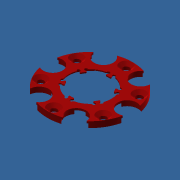
# Autodesk Inventor part: 15-0012-0330
Saved by Autodesk Inventor 2016 SP2 (Build 200236200, 236)
## iProperties
Created: 2017-10-24
Part Number: 15-0012-0330
Material: Plastic (PEEK)
Document SubType Name: Modeling
Designer: Hans Ellermeijer
Density: 1.32 g/cm^3
Appearance: Red
User Status: CNC
Project: Quantum Gas Microscope
Cost Center: 15-0012
Authority: Georgios Siviloglou
Mass: 1.27585 g
Surface Area: 19.8517 cm^2
Volume: 0.966551 cm^3
Description: Aandruk Ring
Category: IOP
Company: Universiteit van Amsterdam
Author: Hans Ellermeijer
Revision Number: A.1
Title: Quantum Gas Microscope
Autodesk Inventor part; units mm, degrees
ref_plane "YZ Plane" through (0, 0, 0) normal (1, 0, 0) x (0, 1, 0)
ref_plane "XZ Plane" through (0, 0, 0) normal (0, 1, 0) x (-1, 0, 0)
ref_plane "XY Plane" through (0, 0, 0) normal (0, 0, 1) x (1, 0, 0)
sketch "Sketch1" plane through (0, 0, 0) normal (0, 0, 1) x (1, 0, 0)
  line L0 (0, 28) -> (0, -28) construction
  line L1 (-31.06, 0) -> (28.51, 0) construction
  circle A0 centre (0, 0) radius 8.5
  circle A1 centre (0, 0) radius 10
  circle A2 centre (0, 0) radius 20
  line L2 (0, 0) -> (-1.1095, 8.4273) construction
  line L3 (0, 0) -> (1.1095, 8.4273) construction
  line L4 (-1.1095, 8.4273) -> (-1.3053, 9.9144)
  line L5 (1.1095, 8.4273) -> (1.3053, 9.9144)
  circle A3 centre (-1.3053, 9.9144) radius 0.7
  circle A4 centre (1.3053, 9.9144) radius 0.7
  line L6 (-7.5, 12.9904) -> (0, 0) construction
  circle A5 centre (-17.5, 0) radius 5.05
  point P0 (0, 17)
  dimension "d0" = 17
  dimension "d1" = 20
  dimension "d2" = 40
  dimension "d3" = 15
  dimension "d4" = 7.5
  dimension "d12" = 17
  dimension "d21" = 1.4
  dimension "d22" = 1.4
  dimension "d34" = 15
  dimension "d35" = 60
  dimension "d51" = 10.1
  dimension "d52" = 17.5
  constraints: 10 end point, 6 centre point, 4 coincident, 4 point on circle, 2 collinear, 2 point on line, 1 concentric, 1 midpoint
  measures "d0" diameter of A0
  measures "d1" diameter of A1
  measures "d2" diameter of A2
  measures "d3" angle of L5 L4
  measures "d4" angle of L0 L4
  measures "d12" distance from line of point (0, 17) L1
  measures "d21" diameter of A3
  measures "d22" diameter of A4
  measures "d34" distance of A0.centre L6.start
  measures "d35" angle of L6 L1
  measures "d51" diameter of A5
  measures "d52" distance from line of A5.centre L0
extrude "Extrusion1" add sketch "Sketch1" along normal blind 0.5 contours A1 A4 | A1 A3 | A2 A5 | A5 A2 picked at (-12.5533, 7.832) picked at (-17.4424, 0)
extrude "Extrusion2" add sketch "Sketch1" along normal blind 0.5 contours A0 L4 A3 A1 A4 L5 | A4 A1 L5 | L4 A1 A3 picked at (0.1331, 9.2081) picked at (1.148, 9.7045) picked at (-1.1435, 9.7062)
hole "Hole1" at (0, 17, 0) direction (0, 0, 1) diameter 3.1 end through all
extrude "Extrusion3" cut sketch "Sketch1" along normal through all contours A4 A1 L5 | L5 A1 A4 | A3 A1 L4 | L4 A1 A3 | A1 A4 | A1 A3
fillet "Fillet2" radius 0.5 4 edges at (-1.9957, 9.7988, 0.25) (-1.2139, 9.2204, 0.25) (1.9957, 9.7988, 0.25) (1.2139, 9.2204, 0.25)
fillet "Fillet3" radius 0.3 2 edges at (-1.1095, 8.4273, 0.25) (1.1095, 8.4273, 0.25)
pattern_circular "Circular Pattern1" count 6 over 360 about axis through (0, 0, -10) along (0, 0, 1) of "Extrusion2", "Hole1", "Extrusion3", "Fillet2", "Fillet3"
sketch "Sketch2" plane through (0, 0, 0) normal (0, 0, -1) x (-1, 0, 0)
  arc A0 (-8.5393, 3.8528) -> (-8.231, 3.4094) centre (-8.0396, 3.8713) ccw projected
  line L0 (-8.1254, 3.3657) -> (-8.231, 3.4094) projected
  arc A1 (-6.916, 4.9416) -> (-7.7375, 3.5186) centre (0, 0) ccw projected
  line L1 (-7.0681, 5.4235) -> (-6.9775, 5.354) projected
  arc A2 (-7.0681, 5.4235) -> (-7.6062, 5.4688) centre (-7.3725, 5.0269) ccw projected
  arc A3 (-7.741, 6.7606) -> (-7.6062, 5.4688) centre (-7.9335, 6.0876) ccw projected
  arc A4 (-7.741, 6.7606) -> (-7.2414, 6.8965) centre (-7.6035, 7.2413) ccw projected
  arc A5 (-2.3518, 9.7195) -> (-7.2414, 6.8965) centre (0, 0) ccw projected
  arc A6 (-2.3518, 9.7195) -> (-1.9844, 10.0842) centre (-2.4694, 10.2055) ccw projected
  arc A7 (-0.933, 9.3216) -> (-1.9844, 10.0842) centre (-1.3053, 9.9144) ccw projected
  arc A8 (-0.933, 9.3216) -> (-1.1629, 8.8329) centre (-0.6672, 8.8982) ccw projected
  line L2 (-1.148, 8.7196) -> (-1.1629, 8.8329) projected
  arc A9 (0.8215, 8.4602) -> (-0.8215, 8.4602) centre (0, 0) ccw projected
  line L3 (1.1629, 8.8329) -> (1.148, 8.7196) projected
  arc A10 (1.1629, 8.8329) -> (0.933, 9.3216) centre (0.6672, 8.8982) ccw projected
  arc A11 (1.9844, 10.0842) -> (0.933, 9.3216) centre (1.3053, 9.9144) ccw projected
  arc A12 (1.9844, 10.0842) -> (2.3518, 9.7195) centre (2.4694, 10.2055) ccw projected
  arc A13 (7.2414, 6.8965) -> (2.3518, 9.7195) centre (0, 0) ccw projected
  arc A14 (7.2414, 6.8965) -> (7.741, 6.7606) centre (7.6035, 7.2413) ccw projected
  arc A15 (7.6062, 5.4688) -> (7.741, 6.7606) centre (7.9335, 6.0876) ccw projected
  arc A16 (7.6062, 5.4688) -> (7.0681, 5.4235) centre (7.3725, 5.0269) ccw projected
  line L4 (6.9775, 5.354) -> (7.0681, 5.4235) projected
  arc A17 (7.7375, 3.5186) -> (6.916, 4.9416) centre (0, 0) ccw projected
  line L5 (8.231, 3.4094) -> (8.1254, 3.3657) projected
  arc A18 (8.231, 3.4094) -> (8.5393, 3.8528) centre (8.0396, 3.8713) ccw projected
  arc A19 (9.7254, 3.3236) -> (8.5393, 3.8528) centre (9.2388, 3.8268) ccw projected
  arc A20 (9.7254, 3.3236) -> (9.5933, 2.823) centre (10.0729, 2.9641) ccw projected
  arc A21 (9.5933, -2.823) -> (9.5933, 2.823) centre (0, 0) ccw projected
  arc A22 (9.5933, -2.823) -> (9.7254, -3.3236) centre (10.0729, -2.9641) ccw projected
  arc A23 (8.5393, -3.8528) -> (9.7254, -3.3236) centre (9.2388, -3.8268) ccw projected
  arc A24 (8.5393, -3.8528) -> (8.231, -3.4094) centre (8.0396, -3.8713) ccw projected
  line L6 (8.1254, -3.3657) -> (8.231, -3.4094) projected
  arc A25 (6.916, -4.9416) -> (7.7375, -3.5186) centre (0, 0) ccw projected
  line L7 (7.0681, -5.4235) -> (6.9775, -5.354) projected
  arc A26 (7.0681, -5.4235) -> (7.6062, -5.4688) centre (7.3725, -5.0269) ccw projected
  arc A27 (7.741, -6.7606) -> (7.6062, -5.4688) centre (7.9335, -6.0876) ccw projected
  arc A28 (7.741, -6.7606) -> (7.2414, -6.8965) centre (7.6035, -7.2413) ccw projected
  arc A29 (2.3518, -9.7195) -> (7.2414, -6.8965) centre (0, 0) ccw projected
  arc A30 (2.3518, -9.7195) -> (1.9844, -10.0842) centre (2.4694, -10.2055) ccw projected
  arc A31 (0.933, -9.3216) -> (1.9844, -10.0842) centre (1.3053, -9.9144) ccw projected
  arc A32 (0.933, -9.3216) -> (1.1629, -8.8329) centre (0.6672, -8.8982) ccw projected
  line L8 (1.148, -8.7196) -> (1.1629, -8.8329) projected
  arc A33 (-0.8215, -8.4602) -> (0.8215, -8.4602) centre (0, 0) ccw projected
  line L9 (-1.1629, -8.8329) -> (-1.148, -8.7196) projected
  arc A34 (-1.1629, -8.8329) -> (-0.933, -9.3216) centre (-0.6672, -8.8982) ccw projected
  arc A35 (-1.9844, -10.0842) -> (-0.933, -9.3216) centre (-1.3053, -9.9144) ccw projected
  arc A36 (-1.9844, -10.0842) -> (-2.3518, -9.7195) centre (-2.4694, -10.2055) ccw projected
  arc A37 (-7.2414, -6.8965) -> (-2.3518, -9.7195) centre (0, 0) ccw projected
  arc A38 (-7.2414, -6.8965) -> (-7.741, -6.7606) centre (-7.6035, -7.2413) ccw projected
  arc A39 (-7.6062, -5.4688) -> (-7.741, -6.7606) centre (-7.9335, -6.0876) ccw projected
  arc A40 (-7.6062, -5.4688) -> (-7.0681, -5.4235) centre (-7.3725, -5.0269) ccw projected
  line L10 (-6.9775, -5.354) -> (-7.0681, -5.4235) projected
  arc A41 (-7.7375, -3.5186) -> (-6.916, -4.9416) centre (0, 0) ccw projected
  line L11 (-8.231, -3.4094) -> (-8.1254, -3.3657) projected
  arc A42 (-8.231, -3.4094) -> (-8.5393, -3.8528) centre (-8.0396, -3.8713) ccw projected
  arc A43 (-9.7254, -3.3236) -> (-8.5393, -3.8528) centre (-9.2388, -3.8268) ccw projected
  arc A44 (-9.7254, -3.3236) -> (-9.5933, -2.823) centre (-10.0729, -2.9641) ccw projected
  arc A45 (-9.5933, 2.823) -> (-9.5933, -2.823) centre (0, 0) ccw projected
  arc A46 (-9.5933, 2.823) -> (-9.7254, 3.3236) centre (-10.0729, 2.9641) ccw projected
  arc A47 (-8.5393, 3.8528) -> (-9.7254, 3.3236) centre (-9.2388, 3.8268) ccw projected
  circle A48 centre (0, 0) radius 20 projected
  circle A49 centre (0, 17) radius 1.55 projected
  circle A50 centre (14.7224, 8.5) radius 1.55 projected
  circle A51 centre (14.7224, -8.5) radius 1.55 projected
  circle A52 centre (0, -17) radius 1.55 projected
  circle A53 centre (-14.7224, -8.5) radius 1.55 projected
  circle A54 centre (-14.7224, 8.5) radius 1.55 projected
  circle A55 centre (0, 0) radius 13
  arc A56 (-8.1254, 3.3657) -> (-7.7375, 3.5186) centre (-8.0106, 3.6428) ccw projected
  arc A57 (-6.916, 4.9416) -> (-6.9775, 5.354) centre (-7.1601, 5.116) ccw projected
  arc A58 (-1.148, 8.7196) -> (-0.8215, 8.4602) centre (-0.8505, 8.7588) ccw projected
  arc A59 (0.8215, 8.4602) -> (1.148, 8.7196) centre (0.8505, 8.7588) ccw projected
  arc A60 (6.9775, 5.354) -> (6.916, 4.9416) centre (7.1601, 5.116) ccw projected
  arc A61 (7.7375, 3.5186) -> (8.1254, 3.3657) centre (8.0106, 3.6428) ccw projected
  arc A62 (8.1254, -3.3657) -> (7.7375, -3.5186) centre (8.0106, -3.6428) ccw projected
  arc A63 (6.916, -4.9416) -> (6.9775, -5.354) centre (7.1601, -5.116) ccw projected
  arc A64 (1.148, -8.7196) -> (0.8215, -8.4602) centre (0.8505, -8.7588) ccw projected
  arc A65 (-0.8215, -8.4602) -> (-1.148, -8.7196) centre (-0.8505, -8.7588) ccw projected
  arc A66 (-6.9775, -5.354) -> (-6.916, -4.9416) centre (-7.1601, -5.116) ccw projected
  arc A67 (-7.7375, -3.5186) -> (-8.1254, -3.3657) centre (-8.0106, -3.6428) ccw projected
  circle A68 centre (7.5, 12.9904) radius 4 projected
  dimension "d27" = 26
  constraints: 1 centre point, 1 coincident
  measures "d27" diameter of A55
extrude "Extrusion4" add sketch "Sketch2" along normal blind 2.3 contours A48 | A55 A68 picked at (7.6136, 12.8802)
chamfer "Chamfer1" distance 1.4 angle 45 6 edges at (0, 15.45, 0.5) (-13.3801, 7.725, 0.5) (-13.3801, -7.725, 0.5) (0, -15.45, 0.5) (13.3801, -7.725, 0.5) (13.3801, 7.725, 0.5)
sketch "Sketch4" plane through (0, 0, 0.5) normal (0, 0, 1) x (1, 0, 0)
  line L0 (0, 28) -> (0, -28) construction
  line L1 (-30.4, 0) -> (28.4, 0) construction
  circle A0 centre (-17.5, 0) radius 4.5
  point P0 (0, 0)
  dimension "d42" = 9
  dimension "d43" = 17.5
  constraints: 1 centre point, 1 point on line
  measures "d42" diameter of A0
  measures "d43" distance from line of L0 A0.centre
extrude "Extrusion6" cut sketch "Sketch4" against normal through all
pattern_circular "Circular Pattern2" count 6 over 360 about axis through (0, 0, -10) along (0, 0, 1) of "Extrusion6"
fillet "Fillet4" radius 0.1 12 edges at (19.6, -3.9799, -0.9) (19.6, 3.9799, -0.9) (6.3533, -18.9641, -0.9) (13.2467, -14.9841, -0.9) (-6.3533, -18.9641, -0.9) (-13.2467, -14.9841, -0.9) (-19.6, -3.9799, -0.9) (-19.6, 3.9799, -0.9) (-13.2467, 14.9841, -0.9) (-6.3533, 18.9641, -0.9) (6.3533, 18.9641, -0.9) (13.2467, 14.9841, -0.9)
sketch "Sketch5" plane through (0, 0, 0) normal (0, 0, -1) x (-1, 0, 0)
  circle A0 centre (0, 0) radius 10.8677 construction
  constraints: 1 centre point, 1 coincident
extrude "Extrusion7" cut sketch "Sketch1" against normal blind 5 contours A5 A2 | A2 A5 picked at (-17.4424, 0) picked at (-20.8091, 0)
pattern_circular "Circular Pattern3" count 6 over 360 about axis through (0, 0, -10) along (0, 0, 1) of "Extrusion7"
sketch "Sketch6" plane through (0, 0, 0) normal (0, 0, -1) x (-1, 0, 0)
  arc A0 (19.4174, 4.0711) -> (19.4174, -4.0711) centre (17.5, 0) ccw projected
  arc A1 (-8.1254, 3.3657) -> (-7.7375, 3.5186) centre (-8.0106, 3.6428) ccw projected
  arc A2 (-6.916, 4.9416) -> (-7.7375, 3.5186) centre (0, 0) ccw projected
  arc A3 (-6.916, 4.9416) -> (-6.9775, 5.354) centre (-7.1601, 5.116) ccw projected
  line L0 (-7.0681, 5.4235) -> (-6.9775, 5.354) projected
  arc A4 (-7.0681, 5.4235) -> (-7.6062, 5.4688) centre (-7.3725, 5.0269) ccw projected
  arc A5 (-7.741, 6.7606) -> (-7.6062, 5.4688) centre (-7.9335, 6.0876) ccw projected
  arc A6 (-7.741, 6.7606) -> (-7.2414, 6.8965) centre (-7.6035, 7.2413) ccw projected
  arc A7 (-2.3518, 9.7195) -> (-7.2414, 6.8965) centre (0, 0) ccw projected
  arc A8 (-2.3518, 9.7195) -> (-1.9844, 10.0842) centre (-2.4694, 10.2055) ccw projected
  arc A9 (-0.933, 9.3216) -> (-1.9844, 10.0842) centre (-1.3053, 9.9144) ccw projected
  arc A10 (-0.933, 9.3216) -> (-1.1629, 8.8329) centre (-0.6672, 8.8982) ccw projected
  line L1 (-1.148, 8.7196) -> (-1.1629, 8.8329) projected
  arc A11 (-1.148, 8.7196) -> (-0.8215, 8.4602) centre (-0.8505, 8.7588) ccw projected
  arc A12 (0.8215, 8.4602) -> (-0.8215, 8.4602) centre (0, 0) ccw projected
  arc A13 (0.8215, 8.4602) -> (1.148, 8.7196) centre (0.8505, 8.7588) ccw projected
  line L2 (1.1629, 8.8329) -> (1.148, 8.7196) projected
  arc A14 (1.1629, 8.8329) -> (0.933, 9.3216) centre (0.6672, 8.8982) ccw projected
  arc A15 (1.9844, 10.0842) -> (0.933, 9.3216) centre (1.3053, 9.9144) ccw projected
  arc A16 (1.9844, 10.0842) -> (2.3518, 9.7195) centre (2.4694, 10.2055) ccw projected
  arc A17 (7.2414, 6.8965) -> (2.3518, 9.7195) centre (0, 0) ccw projected
  arc A18 (7.2414, 6.8965) -> (7.741, 6.7606) centre (7.6035, 7.2413) ccw projected
  arc A19 (7.6062, 5.4688) -> (7.741, 6.7606) centre (7.9335, 6.0876) ccw projected
  arc A20 (7.6062, 5.4688) -> (7.0681, 5.4235) centre (7.3725, 5.0269) ccw projected
  line L3 (6.9775, 5.354) -> (7.0681, 5.4235) projected
  arc A21 (6.9775, 5.354) -> (6.916, 4.9416) centre (7.1601, 5.116) ccw projected
  arc A22 (7.7375, 3.5186) -> (6.916, 4.9416) centre (0, 0) ccw projected
  arc A23 (7.7375, 3.5186) -> (8.1254, 3.3657) centre (8.0106, 3.6428) ccw projected
  line L4 (8.231, 3.4094) -> (8.1254, 3.3657) projected
  arc A24 (8.231, 3.4094) -> (8.5393, 3.8528) centre (8.0396, 3.8713) ccw projected
  arc A25 (9.7254, 3.3236) -> (8.5393, 3.8528) centre (9.2388, 3.8268) ccw projected
  arc A26 (9.7254, 3.3236) -> (9.5933, 2.823) centre (10.0729, 2.9641) ccw projected
  arc A27 (9.5933, -2.823) -> (9.5933, 2.823) centre (0, 0) ccw projected
  arc A28 (9.5933, -2.823) -> (9.7254, -3.3236) centre (10.0729, -2.9641) ccw projected
  arc A29 (8.5393, -3.8528) -> (9.7254, -3.3236) centre (9.2388, -3.8268) ccw projected
  arc A30 (8.5393, -3.8528) -> (8.231, -3.4094) centre (8.0396, -3.8713) ccw projected
  line L5 (8.1254, -3.3657) -> (8.231, -3.4094) projected
  arc A31 (8.1254, -3.3657) -> (7.7375, -3.5186) centre (8.0106, -3.6428) ccw projected
  arc A32 (6.916, -4.9416) -> (7.7375, -3.5186) centre (0, 0) ccw projected
  arc A33 (6.916, -4.9416) -> (6.9775, -5.354) centre (7.1601, -5.116) ccw projected
  line L6 (7.0681, -5.4235) -> (6.9775, -5.354) projected
  arc A34 (7.0681, -5.4235) -> (7.6062, -5.4688) centre (7.3725, -5.0269) ccw projected
  arc A35 (7.741, -6.7606) -> (7.6062, -5.4688) centre (7.9335, -6.0876) ccw projected
  arc A36 (7.741, -6.7606) -> (7.2414, -6.8965) centre (7.6035, -7.2413) ccw projected
  arc A37 (2.3518, -9.7195) -> (7.2414, -6.8965) centre (0, 0) ccw projected
  arc A38 (2.3518, -9.7195) -> (1.9844, -10.0842) centre (2.4694, -10.2055) ccw projected
  arc A39 (0.933, -9.3216) -> (1.9844, -10.0842) centre (1.3053, -9.9144) ccw projected
  arc A40 (0.933, -9.3216) -> (1.1629, -8.8329) centre (0.6672, -8.8982) ccw projected
  line L7 (1.148, -8.7196) -> (1.1629, -8.8329) projected
  arc A41 (1.148, -8.7196) -> (0.8215, -8.4602) centre (0.8505, -8.7588) ccw projected
  arc A42 (-0.8215, -8.4602) -> (0.8215, -8.4602) centre (0, 0) ccw projected
  arc A43 (-0.8215, -8.4602) -> (-1.148, -8.7196) centre (-0.8505, -8.7588) ccw projected
  line L8 (-1.1629, -8.8329) -> (-1.148, -8.7196) projected
  arc A44 (-1.1629, -8.8329) -> (-0.933, -9.3216) centre (-0.6672, -8.8982) ccw projected
  arc A45 (-1.9844, -10.0842) -> (-0.933, -9.3216) centre (-1.3053, -9.9144) ccw projected
  arc A46 (-1.9844, -10.0842) -> (-2.3518, -9.7195) centre (-2.4694, -10.2055) ccw projected
  arc A47 (-7.2414, -6.8965) -> (-2.3518, -9.7195) centre (0, 0) ccw projected
  arc A48 (-7.2414, -6.8965) -> (-7.741, -6.7606) centre (-7.6035, -7.2413) ccw projected
  arc A49 (-7.6062, -5.4688) -> (-7.741, -6.7606) centre (-7.9335, -6.0876) ccw projected
  arc A50 (-7.6062, -5.4688) -> (-7.0681, -5.4235) centre (-7.3725, -5.0269) ccw projected
  line L9 (-6.9775, -5.354) -> (-7.0681, -5.4235) projected
  arc A51 (-6.9775, -5.354) -> (-6.916, -4.9416) centre (-7.1601, -5.116) ccw projected
  arc A52 (-7.7375, -3.5186) -> (-6.916, -4.9416) centre (0, 0) ccw projected
  arc A53 (-7.7375, -3.5186) -> (-8.1254, -3.3657) centre (-8.0106, -3.6428) ccw projected
  line L10 (-8.231, -3.4094) -> (-8.1254, -3.3657) projected
  arc A54 (-8.231, -3.4094) -> (-8.5393, -3.8528) centre (-8.0396, -3.8713) ccw projected
  arc A55 (-9.7254, -3.3236) -> (-8.5393, -3.8528) centre (-9.2388, -3.8268) ccw projected
  arc A56 (-9.7254, -3.3236) -> (-9.5933, -2.823) centre (-10.0729, -2.9641) ccw projected
  arc A57 (-9.5933, 2.823) -> (-9.5933, -2.823) centre (0, 0) ccw projected
  arc A58 (-9.5933, 2.823) -> (-9.7254, 3.3236) centre (-10.0729, 2.9641) ccw projected
  arc A59 (-8.5393, 3.8528) -> (-9.7254, 3.3236) centre (-9.2388, 3.8268) ccw projected
  arc A60 (-8.5393, 3.8528) -> (-8.231, 3.4094) centre (-8.0396, 3.8713) ccw projected
  line L11 (-8.1254, 3.3657) -> (-8.231, 3.4094) projected
  arc A61 (6.183, 18.8515) -> (13.2343, 14.7804) centre (8.75, 15.1554) ccw projected
  arc A62 (6.183, 18.8515) -> (6.1568, 19.0288) centre (6.126, 18.9336) ccw projected
  arc A63 (6.1568, 19.0288) -> (5.6907, 19.1733) centre (0, 0) ccw projected
  arc A64 (5.6907, 19.1733) -> (4.7192, 12.1132) centre (8.75, 15.1554) ccw projected
  arc A65 (4.7192, 12.1132) -> (-4.7192, 12.1132) centre (0, 0) ccw projected
  arc A66 (-4.7192, 12.1132) -> (-5.6907, 19.1733) centre (-8.75, 15.1554) ccw projected
  arc A67 (-5.6907, 19.1733) -> (-6.1568, 19.0288) centre (0, 0) ccw projected
  arc A68 (-6.1568, 19.0288) -> (-6.183, 18.8515) centre (-6.126, 18.9336) ccw projected
  arc A69 (-13.2343, 14.7804) -> (-6.183, 18.8515) centre (-8.75, 15.1554) ccw projected
  arc A70 (-13.2343, 14.7804) -> (-13.401, 14.8463) centre (-13.334, 14.7721) ccw projected
  arc A71 (-13.401, 14.8463) -> (-13.7592, 14.515) centre (0, 0) ccw projected
  arc A72 (-13.7592, 14.515) -> (-8.1307, 10.1436) centre (-8.75, 15.1554) ccw projected
  arc A73 (-8.1307, 10.1436) -> (-12.8499, 1.9696) centre (0, 0) ccw projected
  arc A74 (-12.8499, 1.9696) -> (-19.4499, 4.6584) centre (-17.5, 0) ccw projected
  arc A75 (-19.4499, 4.6584) -> (-19.5578, 4.1825) centre (0, 0) ccw projected
  arc A76 (-19.5578, 4.1825) -> (-19.4174, 4.0711) centre (-19.46, 4.1615) ccw projected
  arc A77 (-19.4174, -4.0711) -> (-19.4174, 4.0711) centre (-17.5, 0) ccw projected
  arc A78 (-19.4174, -4.0711) -> (-19.5578, -4.1825) centre (-19.46, -4.1615) ccw projected
  arc A79 (-19.5578, -4.1825) -> (-19.4499, -4.6584) centre (0, 0) ccw projected
  arc A80 (-19.4499, -4.6584) -> (-12.8499, -1.9696) centre (-17.5, 0) ccw projected
  arc A81 (-12.8499, -1.9696) -> (-8.1307, -10.1436) centre (0, 0) ccw projected
  arc A82 (-8.1307, -10.1436) -> (-13.7592, -14.515) centre (-8.75, -15.1554) ccw projected
  arc A83 (-13.7592, -14.515) -> (-13.401, -14.8463) centre (0, 0) ccw projected
  arc A84 (-13.401, -14.8463) -> (-13.2343, -14.7804) centre (-13.334, -14.7721) ccw projected
  arc A85 (-6.183, -18.8515) -> (-13.2343, -14.7804) centre (-8.75, -15.1554) ccw projected
  arc A86 (-6.183, -18.8515) -> (-6.1568, -19.0288) centre (-6.126, -18.9336) ccw projected
  arc A87 (-6.1568, -19.0288) -> (-5.6907, -19.1733) centre (0, 0) ccw projected
  arc A88 (-5.6907, -19.1733) -> (-4.7192, -12.1132) centre (-8.75, -15.1554) ccw projected
  arc A89 (-4.7192, -12.1132) -> (4.7192, -12.1132) centre (0, 0) ccw projected
  arc A90 (4.7192, -12.1132) -> (5.6907, -19.1733) centre (8.75, -15.1554) ccw projected
  arc A91 (5.6907, -19.1733) -> (6.1568, -19.0288) centre (0, 0) ccw projected
  arc A92 (6.1568, -19.0288) -> (6.183, -18.8515) centre (6.126, -18.9336) ccw projected
  arc A93 (13.2343, -14.7804) -> (6.183, -18.8515) centre (8.75, -15.1554) ccw projected
  arc A94 (13.2343, -14.7804) -> (13.401, -14.8463) centre (13.334, -14.7721) ccw projected
  arc A95 (13.401, -14.8463) -> (13.7592, -14.515) centre (0, 0) ccw projected
  arc A96 (13.7592, -14.515) -> (8.1307, -10.1436) centre (8.75, -15.1554) ccw projected
  arc A97 (8.1307, -10.1436) -> (12.8499, -1.9696) centre (0, 0) ccw projected
  arc A98 (12.8499, -1.9696) -> (19.4499, -4.6584) centre (17.5, 0) ccw projected
  arc A99 (19.4499, -4.6584) -> (19.5578, -4.1825) centre (0, 0) ccw projected
  arc A100 (19.5578, -4.1825) -> (19.4174, -4.0711) centre (19.46, -4.1615) ccw projected
  arc A101 (19.4174, 4.0711) -> (19.4174, -4.0711) centre (17.5, 0) ccw projected
  arc A102 (19.4174, 4.0711) -> (19.5578, 4.1825) centre (19.46, 4.1615) ccw projected
  arc A103 (19.5578, 4.1825) -> (19.4499, 4.6584) centre (0, 0) ccw projected
  arc A104 (19.4499, 4.6584) -> (12.8499, 1.9696) centre (17.5, 0) ccw projected
  arc A105 (12.8499, 1.9696) -> (8.1307, 10.1436) centre (0, 0) ccw projected
  arc A106 (8.1307, 10.1436) -> (13.7592, 14.515) centre (8.75, 15.1554) ccw projected
  arc A107 (13.7592, 14.515) -> (13.401, 14.8463) centre (0, 0) ccw projected
  arc A108 (13.401, 14.8463) -> (13.2343, 14.7804) centre (13.334, 14.7721) ccw projected
  arc A109 (19.4499, 4.6584) -> (19.4499, -4.6584) centre (17.5, 0) ccw
  arc A110 (19.6, 3.9799) -> (19.6, -3.9799) centre (17.5, 0) ccw
  circle A111 centre (0, 0) radius 20
  dimension "d60" = 10.1
  dimension "d61" = 9
  dimension "d62" = 40
  constraints: 8 point on circle, 3 centre point, 3 coincident
  measures "d60" diameter of A109
  measures "d61" diameter of A110
  measures "d62" diameter of A111
extrude "Extrusion8" add sketch "Sketch6" along normal blind 0.4 contours A0 A100 A99 A98 A109 A104 A103 A102 | A102 A111 A110 | A110 A111 A100
fillet "Fillet5" radius 0.1 2 edges at (-19.6, -3.9799, -0.2) (-19.6, 3.9799, -0.2)
pattern_circular "Circular Pattern4" count 6 over 360 about axis through (0, 0, -10) along (0, 0, 1) of "Fillet5", "Extrusion8"
sketch "Sketch3" plane through (0, 0, 0.5) normal (0, 0, 1) x (1, 0, 0)
  line L0 (0, 28) -> (0, -28) construction
  line L1 (-28, 0) -> (28, 0) construction
  circle A0 centre (-8, 13.8564) radius 3
  line L2 (-8, 13.8564) -> (0, 0) construction
  dimension "d37" = 6
  dimension "d38" = 60
  dimension "d39" = 16
  constraints: 2 end point, 1 centre point
  measures "d37" diameter of A0
  measures "d38" angle of L2 L1
  measures "d39" distance of L2.end L2.start
equation "\"d4\" = 0.5 * d3"
equation "\"d22\" = d21"
body "Solid1"
